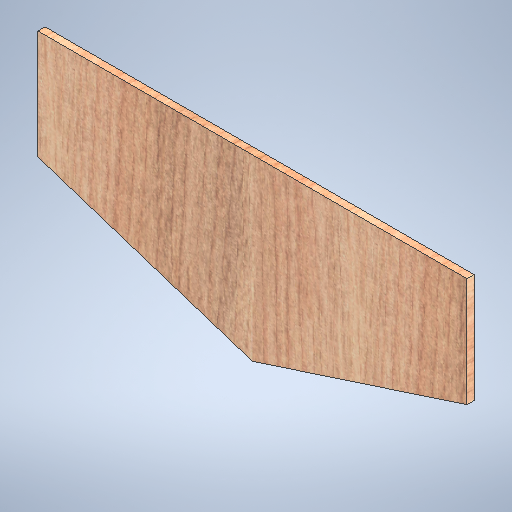
# Autodesk Inventor part: RIB
Saved by Autodesk Inventor 2026.2 (Build 302298000, 298)
## iProperties
Created: 2026-07-30
Part Number: RIB
Material: Wood (Birch)
Document SubType Name: Modeling
Designer: Taiye Raji
Density: 0.6 g/cm^3
Appearance: Birch - Natural Polished
Mass: 554.459 g
Surface Area: 1201.72 cm^2
Volume: 924.098 cm^3
Author: Taiye Raji
Autodesk Inventor part; units mm, degrees
ref_plane "YZ Plane" through (0, 0, 0) normal (1, 0, 0) x (0, 1, 0)
ref_plane "XZ Plane" through (0, 0, 0) normal (0, 1, 0) x (-1, 0, 0)
ref_plane "XY Plane" through (0, 0, 0) normal (0, 0, 1) x (1, 0, 0)
sketch "Sketch1" plane through (0, 0, 0) normal (0, 0, 1) x (1, 0, 0)
  line L0 (180, 0) -> (-180, 0)
  line L1 (0, 0) -> (0, -133) construction
  line L2 (-180, 0) -> (-180, -91.5145)
  line L3 (180, 0) -> (180, -91.5145)
  line L4 (-180, -91.5145) -> (0, -150)
  line L5 (180, -91.5145) -> (0, -150)
  dimension "d0" = 360
  dimension "d1" = 72
  dimension "d2" = 150
  dimension "d3" = 133
  constraints: 12 end point, 3 vertical, 1 horizontal, 1 midpoint, 1 parallel, 1 point on line
  measures "d0" distance of L0.start L0.end
  measures "d1" angle of L4 L1
  measures "d2" distance from line of L4.end L0
  measures "d3" distance of L1.start L1.end
extrude "Extrusion1" add sketch "Sketch1" along normal blind 6
body "Solid1"
